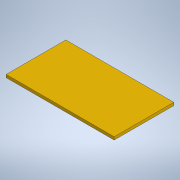
# Autodesk Inventor part: blat_chiuveta
Saved by Autodesk Inventor 2022.6 (Build 266554000, 554)
## iProperties
Created: 2025-08-04
Part Number: blat_chiuveta
Material: Generic
Document SubType Name: Modeling
Designer: Dragos Macovei
Density: 1 g/cm^3
Appearance: Default
Author: Dragos Macovei
Autodesk Inventor part; units mm, degrees
ref_plane "YZ Plane" through (0, 0, 0) normal (1, 0, 0) x (0, 1, 0)
ref_plane "XZ Plane" through (0, 0, 0) normal (0, 1, 0) x (-1, 0, 0)
ref_plane "XY Plane" through (0, 0, 0) normal (0, 0, 1) x (1, 0, 0)
sketch "Sketch1" plane through (0, 0, 0) normal (0, 1, 0) x (-1, 0, 0)
  line L0 (0, 0) -> (670, 0)
  line L1 (670, 0) -> (670, 370)
  line L2 (670, 370) -> (0, 370)
  line L3 (0, 370) -> (0, 0)
  line L4 (335, 0) -> (625, 0)
  line L5 (335, 0) -> (160, 0)
  dimension "d1" = 370
  dimension "d9" = 670
  constraints: 12 end point, 2 parallel, 2 point on line, 1 horizontal, 1 midpoint, 1 perpendicular
  measures "d1" distance of L1.end L0.end
  measures "d9" distance between parallel lines of L3 L1
extrude "Extrusion1" add sketch "Sketch1" along normal blind 18
body "Solid1"
